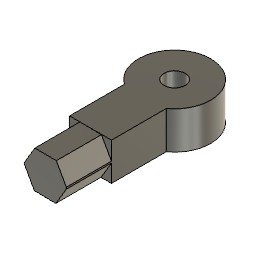
assemble2 (Autodesk Fusion 360 archive; units mm, degrees)
design "eyeend"
part number: 2026-08-27-14-23-14-280
Autodesk Fusion 360 part; units mm, degrees
sketch "Sketch1" plane through (0, 0, 0) normal (0, 0, 1) x (1, 0, 0)
  circle A0 centre (0, 0) radius 24
  circle A1 centre (0, 0) radius 7
  line L0 (0, 0) -> (0, -86)
  line L1 (0, -86) -> (14, -86)
  line L2 (14, -86) -> (-14, -86)
  line L3 (-14, -86) -> (-14, -19.4833)
  line L4 (-14, -19.4833) -> (14, -19.4833)
  line L5 (14, -19.4833) -> (14, -86)
  dimension "d1" = 48
  dimension "d2" = 14
  dimension "d3" = 86
  dimension "d4" = 14
  dimension "d5" = 28
  constraint coincident A0.centre A1.centre
  constraint concentric A0 A1
  constraint vertical L0
  constraint perpendicular L0 L1
  constraint horizontal L2
  constraint vertical L3
  constraint horizontal L4
  constraint vertical L5
  measures "d1" diameter of A0
  measures "d2" diameter of A1
  measures "d3" distance of A0.centre L0.end
  measures "d4" distance of L0.end L1.end
  measures "d5" distance of L1.end L2.end
extrude "Extrude1" add sketch "Sketch1" along normal blind 25
sketch "Sketch2" plane through (0, -86, 0) normal (0, -1, 0) x (1, 0, 0)
  line L0 (-14, 0) -> (14, 0)
  line L1 (14, 0) -> (14, 25)
  line L2 (14, 25) -> (-14, 25)
  line L3 (-14, 25) -> (-14, 0)
  line L4 (0, 0) -> (0, 0.0918)
  line L5 (-14, 12.5) -> (-14, 12.1069)
  line L6 (7, 0) -> (14.3253, 12.3122)
  line L7 (14.3253, 12.3122) -> (7.3253, 24.8122)
  line L8 (7.3253, 24.8122) -> (-7, 25)
  line L9 (-7, 25) -> (-14.3253, 12.6878)
  line L10 (-14.3253, 12.6878) -> (-7.3253, 0.1878)
  line L11 (-7.3253, 0.1878) -> (7, 0)
  point P0 (0, 12.5)
  dimension "d8" = 14
  dimension "d9" = 12.5
  constraint vertical L4
  constraint vertical L5
  constraint coincident L0 L6.start
  constraint coincident L11 L4.end
  constraint coincident L10 L5.end
  measures "d8" distance of L0.start L4.start
  measures "d9" distance of L0.start L5.start
extrude "Extrude2" cut sketch "Sketch2" against normal blind 30 contours L0 L3 L4 L10 L11 | L0 L1 L6 | L2 L3 L9 | L1 L2 L7 L8

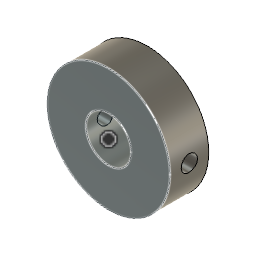
design "coller"
part number: 2026-09-03-13-16-02-014
Autodesk Fusion 360 part; units mm, degrees
sketch "Sketch1" plane through (0, 0, 0) normal (0, 1, 0) x (1, 0, 0)
  circle A0 centre (0, 0) radius 7
  circle A1 centre (0, 0) radius 19
  dimension "d1" = 14
  dimension "d2" = 38
  constraint coincident A0.centre A1.centre
  measures "d1" diameter of A0
  measures "d2" diameter of A1
extrude "Extrude1" add sketch "Sketch1" along normal blind 12 makes body 1
sketch "Sketch2" plane through (0, 0, 0) normal (1, 0, 0) x (0, 1, 0)
  line L0 (0, 19) -> (6, 19)
  line L1 (6, 19) -> (6, 0)
  line L2 (6, 0) -> (0, 0)
  line L3 (0, 0) -> (0, 19)
  circle A0 centre (6, 0) radius 2.5
  dimension "d5" = 6
  dimension "d6" = 5
  constraint horizontal L0
  constraint vertical L1
  constraint horizontal L2
  constraint vertical L3
  constraint coincident L1.end L2.start
  measures "d5" distance of L0.start L0.end
  measures "d6" diameter of A0
extrude "Extrude2" cut sketch "Sketch2" along normal blind 52 and the other way blind 63 contours L1 L2 A0 | L1 L2 A0 bodies 1
extrude "Extrude3" add sketch "Sketch1" along normal blind 12 separate body makes body 2
sketch "Sketch3" plane through (0, 0, 0) normal (1, 0, 0) x (0, 1, 0)
  circle A0 centre (6, 0) radius 2.5
  dimension "d13" = 5
  measures "d13" diameter of A0
extrude "Extrude4" cut sketch "Sketch3" along normal blind 39 and the other way blind 37 bodies 2

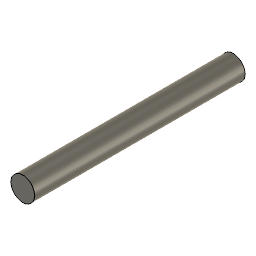
design "tapperpin"
part number: 2026-09-03-13-14-33-161
Autodesk Fusion 360 part; units mm, degrees
sketch "Sketch1" plane through (0, 0, 0) normal (0, 1, 0) x (1, 0, 0)
  circle A0 centre (0, 0) radius 2.5
  dimension "d1" = 5
  constraint coincident A0.centre origin
  measures "d1" diameter of A0
extrude "Extrude1" add sketch "Sketch1" along normal blind 44

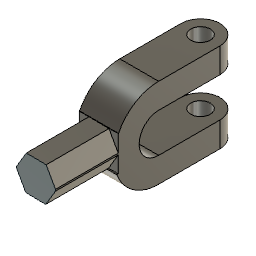
design "fork end"
part number: 2026-08-27-13-21-43-674
Autodesk Fusion 360 part; units mm, degrees
sketch "Sketch1" plane through (0, 0, 0) normal (1, 0, 0) x (0, 1, 0)
  line L0 (0, 14) -> (30, 14)
  line L1 (0, -14) -> (30, -14)
  arc A0 (0, 14) -> (0, -14) centre (0, 0) ccw
  line L2 (30, 14) -> (60, 14)
  line L3 (30, -14) -> (60, -14)
  line L4 (60, 14) -> (60, 32)
  line L5 (60, -14) -> (60, -32)
  line L6 (-14, 0) -> (-32, 0)
  line L7 (60, 32) -> (0, 32)
  line L8 (60, -32) -> (0, -32)
  line L9 (-28.775, 14) -> (-30, 14)
  line L10 (-74, 14) -> (-30, 14)
  line L11 (-30, -11) -> (-74, -11)
  line L12 (-74, -11) -> (-74, 14)
  line L13 (-30, 0) -> (-30, -11)
  arc A1 (0, 32) -> (-28.775, 14) centre (0, 0) ccw
  arc A2 (-30.05, -11) -> (0, -32) centre (0, 0) ccw
  line L14 (30, 14) -> (0, 14)
  line L15 (-28.775, 14) -> (-74, 14)
  dimension "d1" = 28
  dimension "d2" = 30
  dimension "d3" = 30
  dimension "d4" = 30
  dimension "d5" = 30
  dimension "d6" = 18
  dimension "d7" = 18
  dimension "d8" = 18
  dimension "d9" = 25
  dimension "d10" = 104
  constraint coincident A0.centre A1.centre
  constraint horizontal L0
  constraint horizontal L1
  constraint tangent L0 A0
  constraint tangent L1 A0
  constraint parallel L0 L2
  constraint parallel L1 L3
  constraint perpendicular L2 L4
  constraint perpendicular L3 L5
  constraint midpoint A0 L6.start
  constraint horizontal L6
  constraint concentric A0 A1
  constraint tangent L7 A1
  constraint tangent L8 A2
  constraint tangent A0 L9
  constraint horizontal L10
  constraint horizontal L11
  constraint vertical L12
  constraint coincident L6 L13.start
  constraint concentric A1 A2
  constraint coincident L11 A2.start
  constraint collinear L14 L15
  measures "d1" diameter of A0
  measures "d2" distance of L0.start L0.end
  measures "d3" distance of L1.start L1.end
  measures "d4" distance of L0.end L2.end
  measures "d5" distance of L1.end L3.end
  measures "d6" distance of L2.end L4.end
  measures "d7" distance of L3.end L5.end
  measures "d8" distance of L6.start L6.end
  measures "d9" distance of L9.end L11.start
  measures "d10" distance of L0.end L10.start
extrude "Extrude1" add sketch "Sketch1" along normal blind 28
sketch "Sketch2" plane through (0, -74, 0) normal (0, -1, 0) x (1, 0, 0)
  line L0 (0, 14) -> (0, -11)
  line L1 (0, -11) -> (28, -11)
  line L2 (28, -11) -> (28, 14)
  line L3 (28, 14) -> (0, 14)
  line L4 (0, -11) -> (14, -11)
  line L5 (14, -11) -> (14, 1.5)
  line L6 (14, 1.5) -> (0, 1.5)
  line L7 (0, 1.5) -> (0, -11)
  line L8 (21, -11) -> (28.3253, 1.3122)
  line L9 (28.3253, 1.3122) -> (21.3253, 13.8122)
  line L10 (21.3253, 13.8122) -> (7, 14)
  line L11 (7, 14) -> (-0.3253, 1.6878)
  line L12 (-0.3253, 1.6878) -> (6.6747, -10.8122)
  line L13 (6.6747, -10.8122) -> (21, -11)
  point P0 (14, 1.5)
  dimension "d13" = 14
  dimension "d14" = 12.5
  constraint horizontal L4
  constraint vertical L5
  constraint horizontal L6
  constraint vertical L7
  constraint coincident L0.end L1.start
  constraint coincident L1 L8.start
  constraint coincident P0 L5.end
  measures "d13" distance of L0.end L4.end
  measures "d14" distance of L0.end L6.end
extrude "Extrude2" cut sketch "Sketch2" against normal blind 45 contours L0 L3 L11 | L2 L3 L9 L10 | L0 L1 L4 L5 L7 L12 L13 | L1 L2 L8
sketch "Sketch3" plane through (0, 0, 32) normal (0, 0, 1) x (-1, 0, 0)
  line L0 (0, -60) -> (0, 0)
  line L1 (0, 0) -> (-28, 0)
  line L2 (-28, 0) -> (-28, -60)
  line L3 (-28, -60) -> (0, -60)
  line L4 (0, 0) -> (-14, 0)
  line L5 (-14, 0) -> (-14, -30)
  line L6 (0, -44) -> (0, 0)
  circle A0 centre (-14, -44) radius 14
  circle A1 centre (-14, -44) radius 7
  dimension "d17" = 14
  dimension "d18" = 44
  dimension "d19" = 28
  dimension "d20" = 14
  constraint horizontal L4
  constraint vertical L5
  constraint vertical L6
  constraint coincident L0.end L1.start
  constraint concentric A0 A1
  constraint coincident A0 L5.end
  measures "d17" distance of L0.end L4.end
  measures "d18" distance of L0.end L6.start
  measures "d19" diameter of A0
  measures "d20" diameter of A1
extrude "Extrude3" cut sketch "Sketch3" against normal blind 90 contours L0 L2 L3 A0 | A1
sketch "Sketch4" plane through (0, -74, 0) normal (0, -1, 0) x (1, 0, 0)
  line L0 (0, 1.1069) -> (6.6747, -10.8122)
  line L1 (6.6747, -10.8122) -> (14, -10.9082)
  line L2 (14, -10.9082) -> (14, -11)
  line L3 (14, -11) -> (21, -11)
  line L4 (21, -11) -> (28, 0.7654)
  line L5 (28, 0.7654) -> (28, 1.8931)
  line L6 (28, 1.8931) -> (21.3253, 13.8122)
  line L7 (21.3253, 13.8122) -> (7, 14)
  line L8 (7, 14) -> (0, 2.2346)
  line L9 (0, 2.2346) -> (0, 1.1069)
